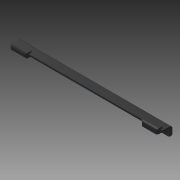
# Autodesk Inventor part: fwd_support
Saved by Autodesk Inventor 2015 (Build 190159000, 159)
## iProperties
Created: 2022-11-04
Part Number: fwd_support
Material: Generic
Document SubType Name: Modeling
Designer: Pavel Brodský
Density: 1 g/cm^3
Appearance: Default
Author: Pavel Brodský
Autodesk Inventor part; units mm, degrees
ref_plane "YZ Plane" through (0, 0, 0) normal (1, 0, 0) x (0, 1, 0)
ref_plane "XZ Plane" through (0, 0, 0) normal (0, 1, 0) x (-1, 0, 0)
ref_plane "XY Plane" through (0, 0, 0) normal (0, 0, 1) x (1, 0, 0)
sketch "Náčrt1" plane through (0, 0, 0) normal (1, 0, 0) x (0, 1, 0)
  line L0 (0, 0) -> (19, 0)
  line L1 (19, 0) -> (19, -19)
  line L2 (19, -19) -> (16, -19)
  line L3 (16, -19) -> (16, -3)
  line L4 (16, -3) -> (0, -3)
  line L5 (0, -3) -> (0, 0)
  dimension "d0" = 19
  dimension "d1" = 19
  dimension "d2" = 3
  dimension "d3" = 3
  constraints: 12 end point, 5 perpendicular, 1 horizontal
  measures "d0" distance of L0.start L0.end
  measures "d1" distance of L0.end L1.end
  measures "d2" distance between parallel lines of L1 L3
  measures "d3" distance of L4.end L0.start
extrude "Vysunutí1" add sketch "Náčrt1" along normal blind 280
fillet "Zaoblení1" radius 5 6 edges at (140, 19, 0) (140, 16, -3) (280, 17.5, -19) (280, 0, -1.5) (0, 17.5, -19) (0, 0, -1.5)
sketch "Náčrt2" plane through (0, 19, -5) normal (0, 1, 0) x (1, 0, 0)
  circle A0 centre (126, 7) radius 2.5
  circle A1 centre (154, 7) radius 2.5
  line L0 (0, -5) -> (0, 0) projected
  line L1 (280, 0) -> (280, -5) projected
  line L2 (0, 0) -> (0, 9) projected
  line L3 (0, -5) -> (280, -5) projected
  dimension "d7" = 5
  dimension "d8" = 5
  dimension "d9" = 28
  dimension "d10" = 280
  dimension "d11" = 126
  dimension "d12" = 12
  constraints: 2 centre point, 1 horizontal alignment
  measures "d7" diameter of A0
  measures "d8" diameter of A1
  measures "d9" distance of A0.centre A1.centre
  measures "d10" distance between parallel lines of L0 L1
  measures "d11" distance from line of L2 A0.centre
  measures "d12" distance from line of A0.centre L3
extrude "Vysunutí2" cut sketch "Náčrt2" against normal through all
sketch "Náčrt3" plane through (0, 5, 0) normal (0, 0, 1) x (1, 0, 0)
  line L0 (4, -10) -> (34, -10)
  line L1 (34, -10) -> (34, 2)
  line L2 (34, 2) -> (4, 2)
  line L3 (4, 2) -> (4, -10)
  line L4 (0, 0) -> (0, 9) projected
  line L5 (5, -5) -> (275, -5) projected
  line L6 (5, 14) -> (275, 14) construction
  line L7 (140, 14) -> (140, -54.0833) construction
  line L8 (276, -10) -> (246, -10)
  line L9 (246, -10) -> (246, 2)
  line L10 (246, 2) -> (276, 2)
  line L11 (276, 2) -> (276, -10)
  point P0 (0, -5)
  dimension "d15" = 30
  dimension "d16" = 4
  dimension "d17" = 5
  dimension "d18" = 12
  constraints: 18 end point, 4 symmetric about line, 2 parallel, 1 horizontal, 1 midpoint, 1 perpendicular, 1 vertical
  measures "d15" distance of L0.start L0.end
  measures "d16" distance between parallel lines of L4 L3
  measures "d17" distance between parallel lines of L0 L5
  measures "d18" distance between parallel lines of L2 L0
extrude "Vysunutí3" add sketch "Náčrt3" along normal blind 3 and the other way blind 6
fillet "Zaoblení2" radius 3 15 edges at (4, 7, 1.5) (34, 7, 1.5) (4, -5, -1.5) (34, -5, -1.5) (4, 7, -4.5) (34, 7, -4.5) (19, -5, 3) (19, -5, -6) (246, 7, 1.5) (276, 7, 1.5) (276, -5, -1.5) (246, -5, -1.5) (261, -5, 3) (276, 7, -4.5) (246, 7, -4.5)
equation "\"d3\" = d2"
equation "\"d11\" = 0.5 * d10 - 0.5 * d9"
